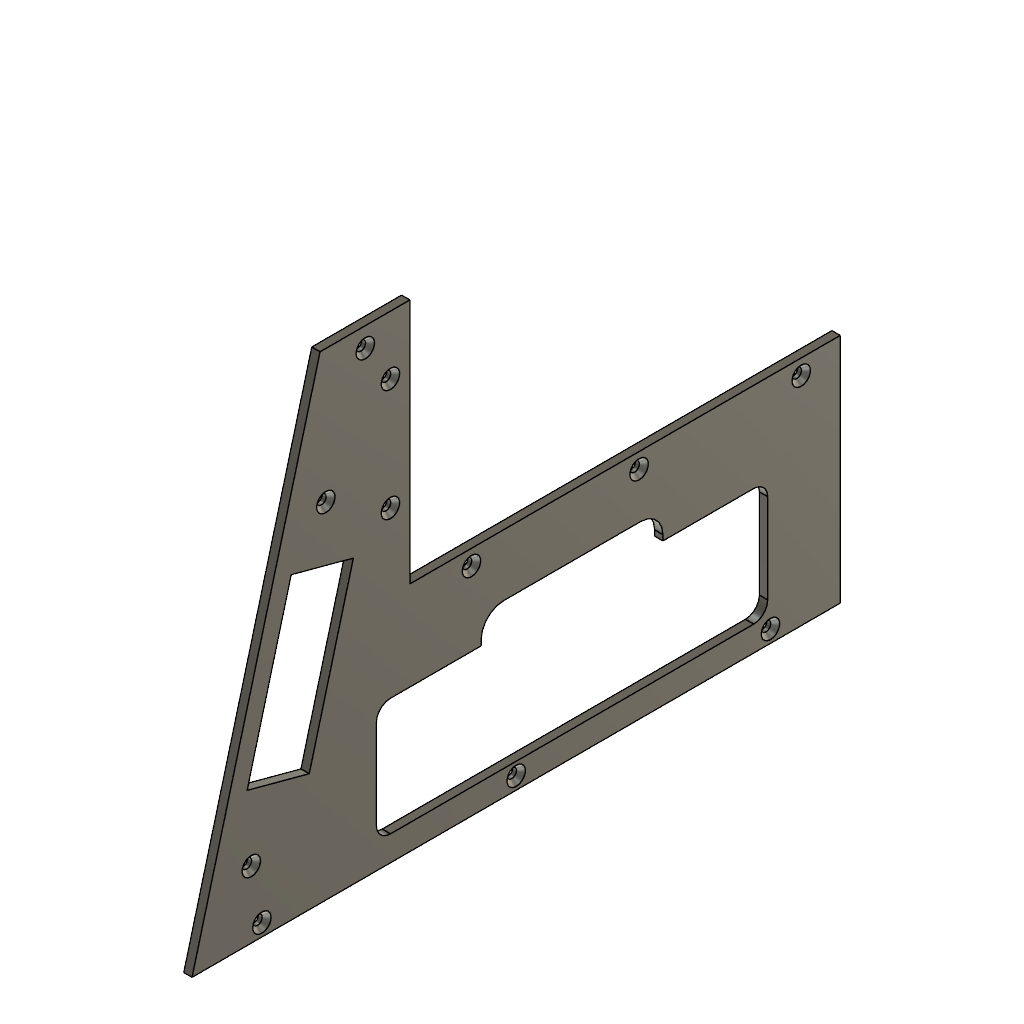
Side_R (Autodesk Fusion 360 design; units mm, degrees)
part number: 2026-10-19-10-28-37-899
Autodesk Fusion 360 part; units mm, degrees
sketch "Side_R_skin" plane through (0, 0, 0) normal (1, 0, 0) x (0, 0, -1)
  line L0 (0, 0) -> (-171, 45.8193)
  line L1 (-171, 45.8193) -> (-171, 78)
  line L2 (-171, 78) -> (-83, 78)
  line L3 (-83, 78) -> (-83, 232)
  line L4 (-83, 232) -> (0, 232)
  line L5 (0, 232) -> (0, 0)
extrude "Side_R_skin (1)" add sketch "Side_R_skin" along normal blind 3 from surface at 101
sketch "Side_R_screws_hole" plane through (0, 0, 0) normal (1, 0, 0) x (0, 0, -1)
  circle A0 centre (-4.5, 25) radius 1.7
  circle A1 centre (-4.5, 116) radius 1.7
  circle A2 centre (-4.5, 207) radius 1.7
  circle A3 centre (-23.908, 21.2106) radius 1.7
  circle A4 centre (-123.3984, 47.8689) radius 1.7
  circle A5 centre (-164, 62) radius 1.7
  circle A6 centre (-110, 71) radius 1.7
  circle A7 centre (-150, 71) radius 1.7
  circle A8 centre (-77.5, 100) radius 1.7
  circle A9 centre (-77.5, 160) radius 1.7
  circle A10 centre (-77.5, 218) radius 1.7
extrude "Side_R_screws_hole (1)" cut sketch "Side_R_screws_hole" against normal blind 4 from surface at 104.5
sketch "Side_R_screws_cone" plane through (0, 0, 0) normal (1, 0, 0) x (0, 0, -1)
  circle A0 centre (-4.5, 25) radius 3.8
  circle A1 centre (-4.5, 116) radius 3.8
  circle A2 centre (-4.5, 207) radius 3.8
  circle A3 centre (-23.908, 21.2106) radius 3.8
  circle A4 centre (-123.3984, 47.8689) radius 3.8
  circle A5 centre (-164, 62) radius 3.8
  circle A6 centre (-110, 71) radius 3.8
  circle A7 centre (-150, 71) radius 3.8
  circle A8 centre (-77.5, 100) radius 3.8
  circle A9 centre (-77.5, 160) radius 3.8
  circle A10 centre (-77.5, 218) radius 3.8
extrude "Side_R_screws_cone (1)" cut sketch "Side_R_screws_cone" against normal blind 2.1 draft -45 from surface at 104.5
sketch "Side_R_door_detent" plane through (0, 0, 0) normal (0, 1, 0) x (1, 0, 0)
  circle A0 centre (101, -30) radius 1.2
  circle A1 centre (101, -62) radius 1.2
extrude "Side_R_door_detent (1)" cut sketch "Side_R_door_detent" along normal blind 2.4 from surface at 229.3
sketch "cassette_window" plane through (0, 0, 0) normal (1, 0, 0) x (0, 0, -1)
  line L0 (-14, 66) -> (-46, 66)
  line L1 (-51, 71) -> (-51, 201)
  line L2 (-46, 206) -> (-14, 206)
  line L3 (-9, 201) -> (-9, 71)
  arc A0 (-51, 71) -> (-46, 66) centre (-46, 71) ccw
  arc A1 (-46, 206) -> (-51, 201) centre (-46, 201) ccw
  arc A2 (-9, 201) -> (-14, 206) centre (-14, 201) ccw
  arc A3 (-14, 66) -> (-9, 71) centre (-14, 71) ccw
  constraint tangent L0 A0
  constraint tangent L1 A0
  constraint tangent L1 A1
  constraint tangent L2 A1
  constraint tangent L2 A2
  constraint tangent L3 A2
  constraint tangent L3 A3
  constraint tangent L0 A3
extrude "cassette_window (1)" cut sketch "cassette_window" along normal blind 4 from surface at 100.5
sketch "cassette_finger_notch" plane through (0, 0, 0) normal (1, 0, 0) x (0, 0, -1)
  line L0 (-47, 103.5) -> (-53, 103.5)
  line L1 (-61, 111.5) -> (-61, 160.5)
  line L2 (-53, 168.5) -> (-47, 168.5)
  line L3 (-39, 160.5) -> (-39, 111.5)
  arc A0 (-61, 111.5) -> (-53, 103.5) centre (-53, 111.5) ccw
  arc A1 (-53, 168.5) -> (-61, 160.5) centre (-53, 160.5) ccw
  arc A2 (-39, 160.5) -> (-47, 168.5) centre (-47, 160.5) ccw
  arc A3 (-47, 103.5) -> (-39, 111.5) centre (-47, 111.5) ccw
  constraint tangent L0 A0
  constraint tangent L1 A0
  constraint tangent L1 A1
  constraint tangent L2 A1
  constraint tangent L2 A2
  constraint tangent L3 A2
  constraint tangent L3 A3
  constraint tangent L0 A3
extrude "cassette_finger_notch (1)" cut sketch "cassette_finger_notch" along normal blind 4 from surface at 100.5
sketch "pi_port_window" plane through (0, 0, 0) normal (1, 0, 0) x (0, 0, -1)
  line L0 (-42.1644, 41.9421) -> (-101.0859, 57.7301)
  line L1 (-101.0859, 57.7301) -> (-107.0387, 35.5138)
  line L2 (-107.0387, 35.5138) -> (-48.1172, 19.7258)
  line L3 (-48.1172, 19.7258) -> (-42.1644, 41.9421)
extrude "pi_port_window (1)" cut sketch "pi_port_window" along normal blind 4 from surface at 100.5
equation "d596 = -( 4.00 mm )"
equation "d599 = -( 2.10 mm )"
named bodies: "Side_R"
